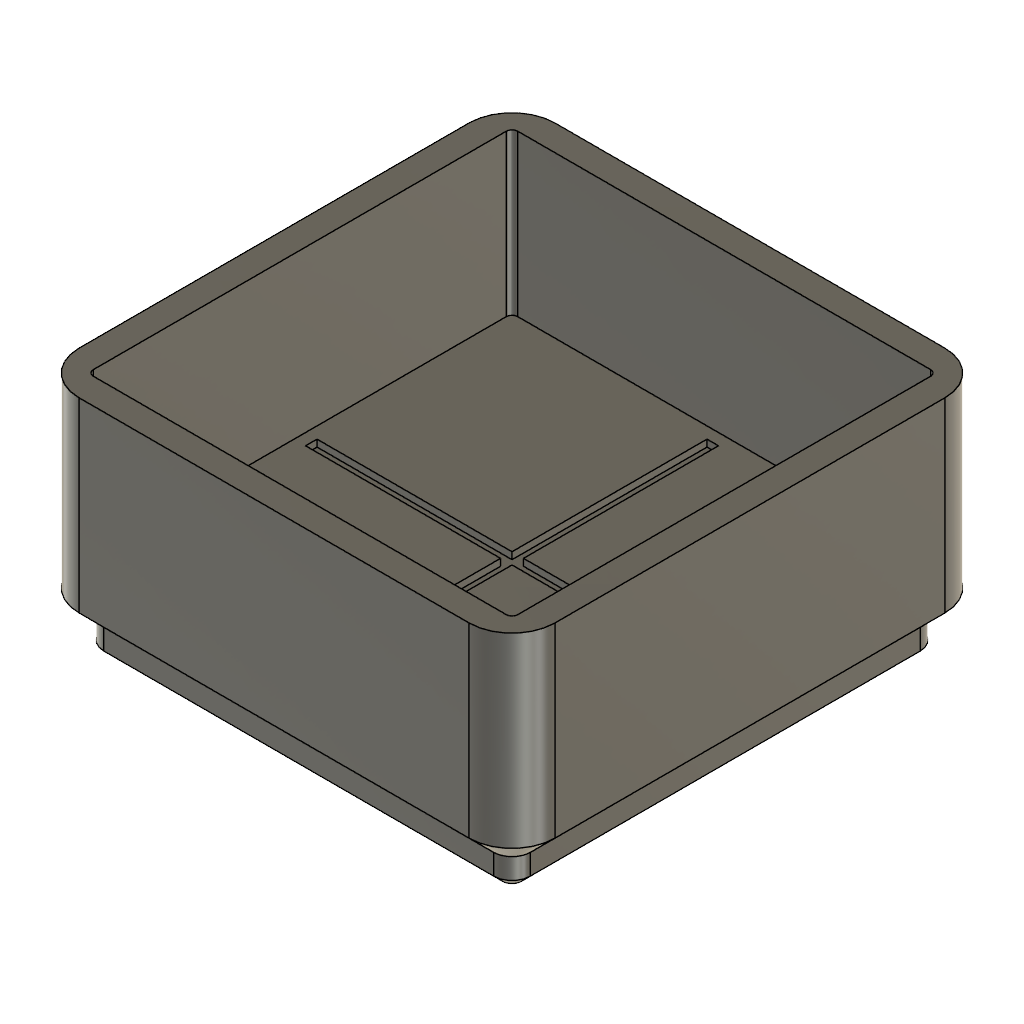
gridfinity-calibration (Autodesk Fusion 360 design; units mm, degrees)
part number: 2026-10-24-15-54-20-376
Autodesk Fusion 360 part; units mm, degrees
ref_plane "WorkPlane1" through (0, 0, 7.039) normal (0, 0, 1) x (1, 0, 0)
sketch "cal_body" plane through (0, 0, 7.039) normal (0, 0, 1) x (1, 0, 0)
  line L0 (-164.5, -42.25) -> (-198.5, -42.25)
  line L1 (-202.25, -46) -> (-202.25, -80)
  line L2 (-198.5, -83.75) -> (-164.5, -83.75)
  line L3 (-160.75, -80) -> (-160.75, -46)
  arc A0 (-198.5, -42.25) -> (-202.25, -46) centre (-198.5, -46) ccw
  arc A1 (-202.25, -80) -> (-198.5, -83.75) centre (-198.5, -80) ccw
  arc A2 (-164.5, -83.75) -> (-160.75, -80) centre (-164.5, -80) ccw
  arc A3 (-160.75, -46) -> (-164.5, -42.25) centre (-164.5, -46) ccw
  constraint tangent L0 A0
  constraint tangent L1 A0
  constraint tangent L1 A1
  constraint tangent L2 A1
  constraint tangent L2 A2
  constraint tangent L3 A2
  constraint tangent L3 A3
  constraint tangent L0 A3
extrude "cal_body (1)" add sketch "cal_body" along normal blind 16.25
ref_plane "WorkPlane2" through (0, 0, 7.039) normal (0, 0, 1) x (1, 0, 0)
sketch "gf_std_foot1" plane through (0, 0, 7.039) normal (0, 0, 1) x (1, 0, 0)
  line L0 (-164.5, -42.25) -> (-198.5, -42.25)
  line L1 (-202.25, -46) -> (-202.25, -80)
  line L2 (-198.5, -83.75) -> (-164.5, -83.75)
  line L3 (-160.75, -80) -> (-160.75, -46)
  arc A0 (-198.5, -42.25) -> (-202.25, -46) centre (-198.5, -46) ccw
  arc A1 (-202.25, -80) -> (-198.5, -83.75) centre (-198.5, -80) ccw
  arc A2 (-164.5, -83.75) -> (-160.75, -80) centre (-164.5, -80) ccw
  arc A3 (-160.75, -46) -> (-164.5, -42.25) centre (-164.5, -46) ccw
  constraint tangent L0 A0
  constraint tangent L1 A0
  constraint tangent L1 A1
  constraint tangent L2 A1
  constraint tangent L2 A2
  constraint tangent L3 A2
  constraint tangent L3 A3
  constraint tangent L0 A3
extrude "gf_std_foot1 (1)" add sketch "gf_std_foot1" against normal blind 2.15 draft -45
ref_plane "WorkPlane3" through (0, 0, 4.889) normal (0, 0, 1) x (1, 0, 0)
sketch "gf_std_foot2" plane through (0, 0, 4.889) normal (0, 0, 1) x (1, 0, 0)
  line L0 (-164.5, -44.4) -> (-198.5, -44.4)
  line L1 (-200.1, -46) -> (-200.1, -80)
  line L2 (-198.5, -81.6) -> (-164.5, -81.6)
  line L3 (-162.9, -80) -> (-162.9, -46)
  arc A0 (-198.5, -44.4) -> (-200.1, -46) centre (-198.5, -46) ccw
  arc A1 (-200.1, -80) -> (-198.5, -81.6) centre (-198.5, -80) ccw
  arc A2 (-164.5, -81.6) -> (-162.9, -80) centre (-164.5, -80) ccw
  arc A3 (-162.9, -46) -> (-164.5, -44.4) centre (-164.5, -46) ccw
  constraint tangent L0 A0
  constraint tangent L1 A0
  constraint tangent L1 A1
  constraint tangent L2 A1
  constraint tangent L2 A2
  constraint tangent L3 A2
  constraint tangent L3 A3
  constraint tangent L0 A3
extrude "gf_std_foot2 (1)" add sketch "gf_std_foot2" against normal blind 1.8
ref_plane "WorkPlane4" through (0, 0, 3.089) normal (0, 0, 1) x (1, 0, 0)
sketch "gf_std_foot3" plane through (0, 0, 3.089) normal (0, 0, 1) x (1, 0, 0)
  line L0 (-164.5, -44.4) -> (-198.5, -44.4)
  line L1 (-200.1, -46) -> (-200.1, -80)
  line L2 (-198.5, -81.6) -> (-164.5, -81.6)
  line L3 (-162.9, -80) -> (-162.9, -46)
  arc A0 (-198.5, -44.4) -> (-200.1, -46) centre (-198.5, -46) ccw
  arc A1 (-200.1, -80) -> (-198.5, -81.6) centre (-198.5, -80) ccw
  arc A2 (-164.5, -81.6) -> (-162.9, -80) centre (-164.5, -80) ccw
  arc A3 (-162.9, -46) -> (-164.5, -44.4) centre (-164.5, -46) ccw
  constraint tangent L0 A0
  constraint tangent L1 A0
  constraint tangent L1 A1
  constraint tangent L2 A1
  constraint tangent L2 A2
  constraint tangent L3 A2
  constraint tangent L3 A3
  constraint tangent L0 A3
extrude "gf_std_foot3 (1)" add sketch "gf_std_foot3" against normal blind 0.8 draft -45
ref_plane "WorkPlane5" through (0, 0, 23.289) normal (0, 0, 1) x (1, 0, 0)
sketch "cal_pocket" plane through (0, 0, 23.289) normal (0, 0, 1) x (1, 0, 0)
  line L0 (-163.5, -44.5) -> (-199.5, -44.5)
  line L1 (-200, -45) -> (-200, -81)
  line L2 (-199.5, -81.5) -> (-163.5, -81.5)
  line L3 (-163, -81) -> (-163, -45)
  arc A0 (-199.5, -44.5) -> (-200, -45) centre (-199.5, -45) ccw
  arc A1 (-200, -81) -> (-199.5, -81.5) centre (-199.5, -81) ccw
  arc A2 (-163.5, -81.5) -> (-163, -81) centre (-163.5, -81) ccw
  arc A3 (-163, -45) -> (-163.5, -44.5) centre (-163.5, -45) ccw
  constraint tangent L0 A0
  constraint tangent L1 A0
  constraint tangent L1 A1
  constraint tangent L2 A1
  constraint tangent L2 A2
  constraint tangent L3 A2
  constraint tangent L3 A3
  constraint tangent L0 A3
extrude "cal_pocket (1)" cut sketch "cal_pocket" against normal blind 14
ref_plane "WorkPlane6" through (0, 0, 9.289) normal (0, 0, 1) x (1, 0, 0)
ref_plane "WorkPlane7" through (0, 0, 9.289) normal (0, 0, 1) x (1, 0, 0)
sketch "cal_cross" plane through (0, 0, 9.289) normal (0, 0, 1) x (1, 0, 0)
  line L0 (-199, -63.5) -> (-164, -63.5)
  line L1 (-164, -63.5) -> (-164, -62.5)
  line L2 (-164, -62.5) -> (-199, -62.5)
  line L3 (-199, -62.5) -> (-199, -63.5)
  line L4 (-182, -80.5) -> (-181, -80.5)
  line L5 (-181, -80.5) -> (-181, -45.5)
  line L6 (-181, -45.5) -> (-182, -45.5)
  line L7 (-182, -45.5) -> (-182, -80.5)
extrude "cal_cross (1)" cut sketch "cal_cross" against normal blind 0.6
named bodies: "gridfinity_calibration_v3"
